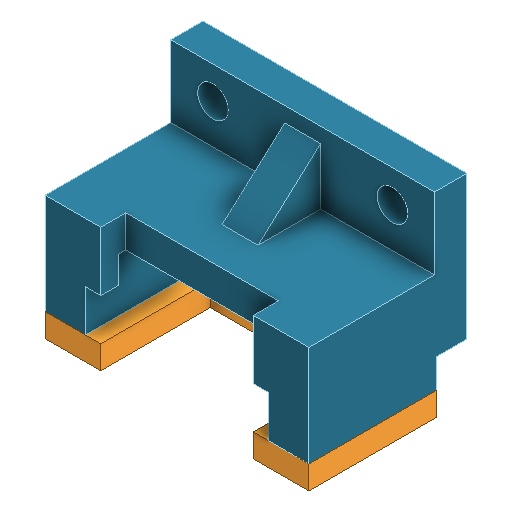
# Autodesk Inventor part: MI-305_Mount_C_Upright_Screw
Saved by Autodesk Inventor 2027 (Build 310192060, 192F)
## iProperties
Created: 2026-11-23
Part Number: MI-305_Mount_C_Upright_Screw
Material: 一般
Document SubType Name: Modeling
Designer: 王翊丞
Density: 1 g/cm^3
Appearance: 預設
Title: MI-305 C 直立螺絲款
Author: 王翊丞
Comments: MI-305 專用。以兩顆 M2 螺絲固定壓片。模型內的底座與壓片是獨立實體。
Autodesk Inventor part; units mm, degrees
ref_plane "直立安裝面" through (0, 0, 0) normal (0, -1, 0) x (1, 0, 0)
sketch "平面安裝底腳草圖" plane through (0, 0, 0) normal (0, 0, 1) x (1, 0, 0)
  line L0 (-14.7, -8) -> (14.7, -8)
  line L1 (14.7, -8) -> (14.7, 8)
  line L2 (14.7, 8) -> (-14.7, 8)
  line L3 (-14.7, 8) -> (-14.7, -8)
  point P0 (0, 0)
  dimension "d0" = 14.7
  dimension "d1" = 8
  dimension "d2" = 29.4
  dimension "d3" = 16
  constraints: 8 end point, 2 parallel, 1 horizontal, 1 perpendicular, 1 other
  measures "d0" horizontal distance of point (0, 0) L0.start
  measures "d1" vertical distance of point (0, 0) L0.start
  measures "d2" distance of L0.start L0.end
  measures "d3" distance of L0.end L1.end
extrude "平面安裝底腳" add sketch "平面安裝底腳草圖" along normal blind 3.6
sketch "直立承板草圖" plane through (0, 0, 0) normal (0, -1, 0) x (1, 0, 0)
  line L0 (-14.7, 3.4) -> (14.7, 3.4)
  line L1 (14.7, 3.4) -> (14.7, 17.6)
  line L2 (14.7, 17.6) -> (-14.7, 17.6)
  line L3 (-14.7, 17.6) -> (-14.7, 3.4)
  point P0 (0, 0)
  dimension "d6" = 14.7
  dimension "d7" = 3.4
  dimension "d8" = 29.4
  dimension "d9" = 14.2
  constraints: 8 end point, 2 parallel, 1 horizontal, 1 perpendicular, 1 other
  measures "d6" horizontal distance of point (0, 0) L0.start
  measures "d7" vertical distance of point (0, 0) L0.start
  measures "d8" distance of L0.start L0.end
  measures "d9" distance of L0.end L1.end
extrude "直立承板" add sketch "直立承板草圖" along normal blind 3.6
ref_plane "承托面" through (0, -3.6, 0) normal (0, -1, 0) x (1, 0, 0)
sketch "USB 插拔避空草圖" plane through (0, -3.6, 0) normal (0, -1, 0) x (1, 0, 0)
  line L0 (-8.5, 14.8) -> (8.5, 14.8)
  line L1 (8.5, 14.8) -> (8.5, 18.6)
  line L2 (8.5, 18.6) -> (-8.5, 18.6)
  line L3 (-8.5, 18.6) -> (-8.5, 14.8)
  point P0 (0, 0)
  dimension "d13" = 8.5
  dimension "d14" = 14.8
  dimension "d15" = 17
  dimension "d16" = 3.8
  constraints: 8 end point, 2 parallel, 1 horizontal, 1 perpendicular, 1 other
  measures "d13" horizontal distance of point (0, 0) L0.start
  measures "d14" vertical distance of point (0, 0) L0.start
  measures "d15" distance of L0.start L0.end
  measures "d16" distance of L0.end L1.end
extrude "USB 插拔避空" cut sketch "USB 插拔避空草圖" against normal blind 3.6
sketch "左側定位壁草圖" plane through (0, -3.6, 0) normal (0, -1, 0) x (1, 0, 0)
  line L0 (-14.7, 3.4) -> (-10.2, 3.4)
  line L1 (-10.2, 3.4) -> (-10.2, 17.6)
  line L2 (-10.2, 17.6) -> (-14.7, 17.6)
  line L3 (-14.7, 17.6) -> (-14.7, 3.4)
  point P0 (0, 0)
  dimension "d19" = 14.7
  dimension "d20" = 3.4
  dimension "d21" = 4.5
  dimension "d22" = 14.2
  constraints: 8 end point, 2 parallel, 1 horizontal, 1 perpendicular, 1 other
  measures "d19" horizontal distance of point (0, 0) L0.start
  measures "d20" vertical distance of point (0, 0) L0.start
  measures "d21" distance of L0.start L0.end
  measures "d22" distance of L0.end L1.end
extrude "左側定位壁" add sketch "左側定位壁草圖" along normal blind 7.65
sketch "右側定位壁草圖" plane through (0, -3.6, 0) normal (0, -1, 0) x (1, 0, 0)
  line L0 (10.2, 3.4) -> (14.7, 3.4)
  line L1 (14.7, 3.4) -> (14.7, 17.6)
  line L2 (14.7, 17.6) -> (10.2, 17.6)
  line L3 (10.2, 17.6) -> (10.2, 3.4)
  point P0 (0, 0)
  dimension "d25" = 10.2
  dimension "d26" = 3.4
  dimension "d27" = 4.5
  dimension "d28" = 14.2
  constraints: 8 end point, 2 parallel, 1 horizontal, 1 perpendicular, 1 other
  measures "d25" horizontal distance of point (0, 0) L0.start
  measures "d26" vertical distance of point (0, 0) L0.start
  measures "d27" distance of L0.start L0.end
  measures "d28" distance of L0.end L1.end
extrude "右側定位壁" add sketch "右側定位壁草圖" along normal blind 7.65
sketch "弧端定位擋塊草圖" plane through (0, -3.6, 0) normal (0, -1, 0) x (1, 0, 0)
  line L0 (-10.2, 3.4) -> (10.2, 3.4)
  line L1 (10.2, 3.4) -> (10.2, 5.4)
  line L2 (10.2, 5.4) -> (-10.2, 5.4)
  line L3 (-10.2, 5.4) -> (-10.2, 3.4)
  point P0 (0, 0)
  dimension "d31" = 10.2
  dimension "d32" = 3.4
  dimension "d33" = 20.4
  dimension "d34" = 2
  constraints: 8 end point, 2 parallel, 1 horizontal, 1 perpendicular, 1 other
  measures "d31" horizontal distance of point (0, 0) L0.start
  measures "d32" vertical distance of point (0, 0) L0.start
  measures "d33" distance of L0.start L0.end
  measures "d34" distance of L0.end L1.end
extrude "弧端定位擋塊" add sketch "弧端定位擋塊草圖" along normal blind 3
sketch "左肩面擋塊草圖" plane through (0, -3.6, 0) normal (0, -1, 0) x (1, 0, 0)
  line L0 (-10.2, 15.6) -> (-8.5, 15.6)
  line L1 (-8.5, 15.6) -> (-8.5, 17.6)
  line L2 (-8.5, 17.6) -> (-10.2, 17.6)
  line L3 (-10.2, 17.6) -> (-10.2, 15.6)
  point P0 (0, 0)
  dimension "d37" = 10.2
  dimension "d38" = 15.6
  dimension "d39" = 1.7
  dimension "d40" = 2
  constraints: 8 end point, 2 parallel, 1 horizontal, 1 perpendicular, 1 other
  measures "d37" horizontal distance of point (0, 0) L0.start
  measures "d38" vertical distance of point (0, 0) L0.start
  measures "d39" distance of L0.start L0.end
  measures "d40" distance of L0.end L1.end
extrude "左肩面擋塊" add sketch "左肩面擋塊草圖" along normal blind 3
sketch "右肩面擋塊草圖" plane through (0, -3.6, 0) normal (0, -1, 0) x (1, 0, 0)
  line L0 (8.5, 15.6) -> (10.2, 15.6)
  line L1 (10.2, 15.6) -> (10.2, 17.6)
  line L2 (10.2, 17.6) -> (8.5, 17.6)
  line L3 (8.5, 17.6) -> (8.5, 15.6)
  point P0 (0, 0)
  dimension "d43" = 8.5
  dimension "d44" = 15.6
  dimension "d45" = 1.7
  dimension "d46" = 2
  constraints: 8 end point, 2 parallel, 1 horizontal, 1 perpendicular, 1 other
  measures "d43" horizontal distance of point (0, 0) L0.start
  measures "d44" vertical distance of point (0, 0) L0.start
  measures "d45" distance of L0.start L0.end
  measures "d46" distance of L0.end L1.end
extrude "右肩面擋塊" add sketch "右肩面擋塊草圖" along normal blind 3
ref_plane "壓片底面" through (0, -11.25, 0) normal (0, -1, 0) x (1, 0, 0)
sketch "側壁 M2 底孔草圖" plane through (0, -11.25, 0) normal (0, -1, 0) x (1, 0, 0)
  circle A0 centre (-12.45, 12.85) radius 0.85
  circle A1 centre (12.45, 12.85) radius 0.85
  point P0 (0, 0)
  dimension "d50" = 12.45
  dimension "d51" = 12.85
  dimension "d52" = 1.7
  dimension "d53" = 12.45
  dimension "d54" = 12.85
  dimension "d55" = 1.7
  constraints: 2 centre point, 1 other
  measures "d50" horizontal distance of point (0, 0) A0.centre
  measures "d51" vertical distance of point (0, 0) A0.centre
  measures "d52" diameter of A0
  measures "d53" horizontal distance of point (0, 0) A1.centre
  measures "d54" vertical distance of point (0, 0) A1.centre
  measures "d55" diameter of A1
extrude "側壁 M2 底孔" cut sketch "側壁 M2 底孔草圖" against normal blind 4.5
ref_plane "底腳頂面" through (0, 0, 3.6) normal (0, 0, 1) x (1, 0, 0)
sketch "底腳 M3 通孔草圖" plane through (0, 0, 3.6) normal (0, 0, 1) x (1, 0, 0)
  circle A0 centre (-10, 4.4) radius 1.7
  circle A1 centre (10, 4.4) radius 1.7
  point P0 (0, 0)
  dimension "d59" = 10
  dimension "d60" = 4.4
  dimension "d61" = 3.4
  dimension "d62" = 10
  dimension "d63" = 4.4
  dimension "d64" = 3.4
  constraints: 2 centre point, 1 other
  measures "d59" horizontal distance of point (0, 0) A0.centre
  measures "d60" vertical distance of point (0, 0) A0.centre
  measures "d61" diameter of A0
  measures "d62" horizontal distance of point (0, 0) A1.centre
  measures "d63" vertical distance of point (0, 0) A1.centre
  measures "d64" diameter of A1
extrude "底腳 M3 通孔" cut sketch "底腳 M3 通孔草圖" against normal blind 3.6
ref_plane "背面補強肋基準" through (-2, 0, 0) normal (1, 0, 0) x (0, 1, 0)
sketch "背面補強肋草圖" plane through (-2, 0, 0) normal (1, 0, 0) x (0, 1, 0)
  line L0 (-0.2, 3.4) -> (6.5, 3.4)
  line L1 (6.5, 3.4) -> (-0.2, 10.8)
  line L2 (-0.2, 10.8) -> (-0.2, 3.4)
  point P0 (0, 0)
  dimension "d67" = 0.2
  dimension "d68" = 3.4
  dimension "d69" = 6.5
  dimension "d70" = 3.4
  dimension "d71" = 0.2
  dimension "d72" = 10.8
  constraints: 6 end point, 1 other
  measures "d67" horizontal distance of point (0, 0) L0.start
  measures "d68" vertical distance of point (0, 0) L0.start
  measures "d69" horizontal distance of point (0, 0) L0.end
  measures "d70" vertical distance of point (0, 0) L0.end
  measures "d71" horizontal distance of point (0, 0) L1.end
  measures "d72" vertical distance of point (0, 0) L1.end
extrude "背面補強肋" add sketch "背面補強肋草圖" along normal blind 4
ref_plane "壓片頂面" through (0, -13.85, 0) normal (0, -1, 0) x (1, 0, 0)
sketch "壓框毛坯草圖" plane through (0, -11.25, 0) normal (0, -1, 0) x (1, 0, 0)
  line L0 (-14.7, 3.4) -> (14.7, 3.4)
  line L1 (14.7, 3.4) -> (14.7, 17.6)
  line L2 (14.7, 17.6) -> (-14.7, 17.6)
  line L3 (-14.7, 17.6) -> (-14.7, 3.4)
  point P0 (0, 0)
  dimension "d76" = 14.7
  dimension "d77" = 3.4
  dimension "d78" = 29.4
  dimension "d79" = 14.2
  constraints: 8 end point, 2 parallel, 1 horizontal, 1 perpendicular, 1 other
  measures "d76" horizontal distance of point (0, 0) L0.start
  measures "d77" vertical distance of point (0, 0) L0.start
  measures "d78" distance of L0.start L0.end
  measures "d79" distance of L0.end L1.end
extrude "壓框毛坯" add sketch "壓框毛坯草圖" along normal blind 2.6 separate body
sketch "U 形開口草圖" plane through (0, -13.85, 0) normal (0, -1, 0) x (1, 0, 0)
  line L0 (-8.5, 5.4) -> (8.5, 5.4)
  line L1 (8.5, 5.4) -> (8.5, 18.6)
  line L2 (8.5, 18.6) -> (-8.5, 18.6)
  line L3 (-8.5, 18.6) -> (-8.5, 5.4)
  point P0 (0, 0)
  dimension "d82" = 8.5
  dimension "d83" = 5.4
  dimension "d84" = 17
  dimension "d85" = 13.2
  constraints: 8 end point, 2 parallel, 1 horizontal, 1 perpendicular, 1 other
  measures "d82" horizontal distance of point (0, 0) L0.start
  measures "d83" vertical distance of point (0, 0) L0.start
  measures "d84" distance of L0.start L0.end
  measures "d85" distance of L0.end L1.end
extrude "U 形開口" cut sketch "U 形開口草圖" against normal blind 2.6 bodies 2
sketch "壓框 M2 通孔草圖" plane through (0, -13.85, 0) normal (0, -1, 0) x (1, 0, 0)
  circle A0 centre (-12.45, 12.85) radius 1.15
  circle A1 centre (12.45, 12.85) radius 1.15
  point P0 (0, 0)
  dimension "d88" = 12.45
  dimension "d89" = 12.85
  dimension "d90" = 2.3
  dimension "d91" = 12.45
  dimension "d92" = 12.85
  dimension "d93" = 2.3
  constraints: 2 centre point, 1 other
  measures "d88" horizontal distance of point (0, 0) A0.centre
  measures "d89" vertical distance of point (0, 0) A0.centre
  measures "d90" diameter of A0
  measures "d91" horizontal distance of point (0, 0) A1.centre
  measures "d92" vertical distance of point (0, 0) A1.centre
  measures "d93" diameter of A1
extrude "壓框 M2 通孔" cut sketch "壓框 M2 通孔草圖" against normal blind 2.6 bodies 2
equation "\"d0\" = BaseHalfX"
equation "\"d1\" = 0.5 * FootDepth"
equation "\"d2\" = 2 * BaseHalfX"
equation "\"d3\" = FootDepth"
equation "\"d4\" = FootThickness"
equation "\"d6\" = BaseHalfX"
equation "\"d7\" = RearY"
equation "\"d8\" = 2 * BaseHalfX"
equation "\"d9\" = FrontY - RearY"
equation "\"d10\" = PlateThickness"
equation "\"d13\" = LipX"
equation "\"d15\" = 2 * LipX"
equation "\"d17\" = PlateThickness"
equation "\"d19\" = OuterX"
equation "\"d20\" = RearY"
equation "\"d21\" = -InnerX + OuterX"
equation "\"d22\" = FrontY - RearY"
equation "\"d23\" = RailTop - PlateThickness"
equation "\"d25\" = InnerX"
equation "\"d26\" = RearY"
equation "\"d27\" = OuterX - InnerX"
equation "\"d28\" = FrontY - RearY"
equation "\"d29\" = RailTop - PlateThickness"
equation "\"d31\" = InnerX"
equation "\"d32\" = RearY"
equation "\"d33\" = 2 * InnerX"
equation "\"d34\" = RearInsideY - RearY"
equation "\"d35\" = StopHeight"
equation "\"d37\" = InnerX"
equation "\"d38\" = FrontInsideY"
equation "\"d39\" = -LipX + InnerX"
equation "\"d40\" = FrontY - FrontInsideY"
equation "\"d41\" = StopHeight"
equation "\"d43\" = LipX"
equation "\"d44\" = FrontInsideY"
equation "\"d45\" = InnerX - LipX"
equation "\"d46\" = FrontY - FrontInsideY"
equation "\"d47\" = StopHeight"
equation "\"d50\" = ScrewX"
equation "\"d51\" = ScrewY"
equation "\"d52\" = KeeperPilot"
equation "\"d53\" = ScrewX"
equation "\"d54\" = ScrewY"
equation "\"d55\" = KeeperPilot"
equation "\"d56\" = KeeperPilotDepth"
equation "\"d59\" = 0.5 * MountPitch"
equation "\"d61\" = MountHole"
equation "\"d62\" = 0.5 * MountPitch"
equation "\"d64\" = MountHole"
equation "\"d65\" = FootThickness"
equation "\"d76\" = OuterX"
equation "\"d77\" = RearY"
equation "\"d78\" = 2 * OuterX"
equation "\"d79\" = FrontY - RearY"
equation "\"d80\" = KeeperThickness"
equation "\"d82\" = LipX"
equation "\"d83\" = RearInsideY"
equation "\"d84\" = 2 * LipX"
equation "\"d86\" = KeeperThickness"
equation "\"d88\" = ScrewX"
equation "\"d89\" = ScrewY"
equation "\"d90\" = KeeperScrewClear"
equation "\"d91\" = ScrewX"
equation "\"d92\" = ScrewY"
equation "\"d93\" = KeeperScrewClear"
equation "\"d94\" = KeeperThickness"
equation "\"HousingWidth\" = 19.8"
equation "\"HousingDepth\" = 9.7"
equation "\"HousingThickness\" = 7.4"
equation "\"FitSide\" = 0.3"
equation "\"FitEnd\" = 0.25"
equation "\"TopClearance\" = 0.25"
equation "\"GripOverlap\" = 1.4"
equation "\"SideWall\" = 4.5"
equation "\"StopWall\" = 2"
equation "\"StopHeight\" = 3"
equation "\"PlateThickness\" = 3.6"
equation "\"KeeperThickness\" = 2.6"
equation "\"KeeperPilot\" = 1.7"
equation "\"KeeperScrewClear\" = 2.3"
equation "\"KeeperPilotDepth\" = 4.5"
equation "\"FootThickness\" = 3.6"
equation "\"FootDepth\" = 16"
equation "\"MountHole\" = 3.4"
equation "\"InnerX\" = 0.5 * HousingWidth + FitSide"
equation "\"OuterX\" = InnerX + SideWall"
equation "\"LipX\" = 0.5 * HousingWidth - GripOverlap"
equation "\"ScrewX\" = InnerX + 0.5 * SideWall"
equation "\"RearY\" = -FitEnd + ShoulderY - HousingDepth - StopWall"
equation "\"RearInsideY\" = RearY + StopWall"
equation "\"FrontInsideY\" = ShoulderY + FitEnd"
equation "\"FrontY\" = FrontInsideY + StopWall"
equation "\"RailTop\" = HousingThickness + PlateThickness + TopClearance"
equation "\"BaseHalfX\" = OuterX"
equation "\"USBOpening\" = 2 * LipX"
equation "\"d12\" = PlateThickness"
equation "\"d49\" = RailTop"
equation "\"d58\" = FootThickness"
equation "\"d75\" = RailTop + KeeperThickness"
equation "\"ShoulderY\" = 15.35"
equation "\"ScrewY\" = 12.85"
equation "\"MountPitch\" = 20"
